Autodesk Fusion 360 part; units mm, degrees
(part 2 of 2)
component "TRACO V1 05 plataforma giratoria" placed x (1, 0, 0) y (0, 1, 0) z (0, 0, 1) at (0, 0, 80)
component "TRACO V1 06 torre direita" placed x (1, 0, 0) y (0, 0, 1) z (0, -1, 0) at (0, 34, 144)
component "TRACO V1 06 torre esquerda" placed x (1, 0, 0) y (0, 0, 1) z (0, -1, 0) at (0, -25, 144)
component "TRACO V1 07 suporte motor base" placed x (1, 0, 0) y (0, 1, 0) z (0, 0, 1) at (-75, 0, 10)
component "TRACO V1 08 suporte motor ombro" placed x (1, 0, 0) y (0, 0, 1) z (0, -1, 0) at (-61, -44, 138)
component "TRACO V1 09 suporte motor cotovelo" placed x (0.6, 0, 0.8) y (-0.8, 0, 0.6) z (0, -1, 0) at (36, -46, 210)
component "TRACO V1 10 braco superior direita" placed x (0.6, 0, 0.8) y (-0.8, 0, 0.6) z (0, -1, 0) at (0, 25, 162)
component "TRACO V1 11 antebraco direita" placed x (0.9, 0, -0.43589) y (0.43589, 0, 0.9) z (0, -1, 0) at (120, 15, 322)
component "TRACO V1 10 braco superior esquerda" placed x (0.6, 0, 0.8) y (-0.8, 0, 0.6) z (0, -1, 0) at (0, -17, 162)
component "TRACO V1 11 antebraco esquerda" placed x (0.9, 0, -0.43589) y (0.43589, 0, 0.9) z (0, -1, 0) at (120, -7, 322)
component "TRACO V1 12 haste paralela superior" placed x (0.6, 0, 0.8) y (-0.8, 0, 0.6) z (0, -1, 0) at (0, 72, 192)
component "TRACO V1 13 haste paralela inferior" placed x (0.9, 0, -0.43589) y (0.43589, 0, 0.9) z (0, -1, 0) at (120, 84, 352)
component "TRACO V1 14 ancora fixa haste" placed x (1, 0, 0) y (0, 0, 1) z (0, -1, 0) at (0, 58, 162)
component "TRACO V1 15 balancim cotovelo" placed x (1, 0, 0) y (0, 0, 1) z (0, -1, 0) at (120, 58, 322)
component "TRACO V1 16 cabeca vertical" placed x (1, 0, 0) y (0, 0, 1) z (0, -1, 0) at (300, 58, 234.822)
component "TRACO V1 17 porta caneta 10mm" placed x (1, 0, 0) y (0, 1, 0) z (0, 0, 1) at (300, 78, 149.822)
component "TRACO V1 18 carenagem superior direita" placed x (0.6, 0, 0.8) y (-0.8, 0, 0.6) z (0, -1, 0) at (0, 42, 162)
component "TRACO V1 20 carenagem base" placed x (1, 0, 0) y (0, 1, 0) z (0, 0, 1) at (0, 0, 76)
component "TRACO V1 21 tampa correia ombro" placed x (0.930566, 0, 0.366124) y (-0.366124, 0, 0.930566) z (0, -1, 0) at (-61, -46, 138)
component "TRACO V1 22 tampa correia cotovelo" placed x (0.6, 0, 0.8) y (-0.8, 0, 0.6) z (0, -1, 0) at (36, -46, 210)
component "TRACO V1 REF motor base 17HS4401" placed x (1, 0, 0) y (0, 1, 0) z (0, 0, 1) at (-75, 0, 18)
component "TRACO V1 REF eixo motor base 5mm" placed x (1, 0, 0) y (0, 1, 0) z (0, 0, 1) at (-75, 0, 58)
component "TRACO V1 REF motor ombro 17HS4401" placed x (1, 0, 0) y (0, 0, 1) z (0, -1, 0) at (-61, -52, 138)
component "TRACO V1 REF eixo motor ombro 5mm" placed x (1, 0, 0) y (0, 0, 1) z (0, -1, 0) at (-61, -28, 138)
component "TRACO V1 REF motor cotovelo 17HS4401" placed x (0.6, 0, 0.8) y (-0.8, 0, 0.6) z (0, -1, 0) at (36, -54, 210)
component "TRACO V1 REF eixo motor cotovelo 5mm" placed x (0.6, 0, 0.8) y (-0.8, 0, 0.6) z (0, -1, 0) at (36, -30, 210)
component "TRACO V1 REF polia J1 100T envelope" placed x (1, 0, 0) y (0, 1, 0) z (0, 0, 1) at (0, 0, 61)
component "TRACO V1 REF polia J2 100T envelope" placed x (1, 0, 0) y (0, 0, 1) z (0, -1, 0) at (0, -36, 162)
component "TRACO V1 REF polia J3 100T envelope" placed x (1, 0, 0) y (0, 0, 1) z (0, -1, 0) at (120, -34, 322)
named bodies: "01 base compacta", "02 mancal inferior", "02a retentor mancal inferior", "03a retentor mancal superior", "03 mancal superior", "04 coluna espaçadora 1", "04 coluna espaçadora 2", "04 coluna espaçadora 3", "04 coluna espaçadora 4", "05 plataforma giratoria", "06 torre direita", "06 torre esquerda", "07 suporte motor base", "08 suporte motor ombro", "09 suporte motor cotovelo", "10 braco superior direita", "11 antebraco direita", "10 braco superior esquerda", "11 antebraco esquerda", "12 haste paralela superior", "13 haste paralela inferior", "14 ancora fixa haste", "15 balancim cotovelo", "16 cabeca vertical", "17 porta caneta 10mm", "18 carenagem superior direita", "20 carenagem base", "21 tampa correia ombro", "22 tampa correia cotovelo", "motor base 17HS4401", "eixo motor base 5mm", "motor ombro 17HS4401", "eixo motor ombro 5mm", "motor cotovelo 17HS4401", "eixo motor cotovelo 5mm", "polia J1 100T envelope", "polia J2 100T envelope", "polia J3 100T envelope"
